Autodesk Fusion 360 part; units mm, degrees
(part 2 of 2)
sketch "Sketch2" plane through (0, 0, 4.8) normal (0, 0, 1) x (1, 0, 0)
  circle A0 centre (0, 0) radius 4.65
  line L0 (-0.4083, 0.4083) -> (-2.45, 0.4083)
  line L1 (-2.45, 0.4083) -> (-2.45, -0.4083)
  line L2 (-2.45, -0.4083) -> (-0.4083, -0.4083)
  line L3 (-0.4083, -0.4083) -> (-0.4083, -2.45)
  line L4 (-0.4083, -2.45) -> (0.4083, -2.45)
  line L5 (0.4083, -2.45) -> (0.4083, -0.4083)
  line L6 (0.4083, -0.4083) -> (2.45, -0.4083)
  line L7 (2.45, -0.4083) -> (2.45, 0.4083)
  line L8 (2.45, 0.4083) -> (0.4083, 0.4083)
  line L9 (0.4083, 0.4083) -> (0.4083, 2.45)
  line L10 (0.4083, 2.45) -> (-0.4083, 2.45)
  line L11 (-0.4083, 2.45) -> (-0.4083, 0.4083)
  dimension "d117" = 360
  dimension "d123" = 0.8167
  dimension "d124" = 4.9
  constraint perpendicular L0 L1
  constraint vertical L0.start L2.end
  constraint horizontal L2
  constraint coincident L0.start L11.end
  measures "d123" distance of L0 L2
  measures "d124" distance of L3.end L10
extrude "Extrude1" add sketch "Sketch2" against normal blind 3.05 draft -4 separate body contours L0 L1 L2 L3 L4 L5 L6 L7 L8 L9 L10 L11 makes body 3
draft "Draft1" angle -30 neutral plane through (0, 0, 4.8) pull (0, 0, 1) 4 faces at (2.3789, 0.065, 3.7833) (0.065, 2.3789, 3.7833) (-2.3789, 0.065, 3.7833) (0.065, -2.3789, 3.7833) on bodies 3
combine "Combine1" operation cut target body 1 tool bodies 2 3
sketch "Sketch6" plane through (0, 0, 4.8) normal (0, 0, 1) x (1, 0, 0)
  circle A0 centre (0, 0) radius 2.4838 construction
  line L0 (0, 0) -> (-1.7563, 1.7563) construction
  line L1 (-1.7563, 1.7563) -> (-0.4083, 0.49)
  line L2 (-0.4083, 0.49) -> (-0.49, 0.4083)
  line L3 (-0.49, 0.4083) -> (-1.7563, 1.7563)
  point P0 (-0.4083, 2.45)
  point P1 (-0.4083, 2.45)
  point P2 (-0.49, 0.49)
  point P3 (-0.4083, 0.49)
  point P4 (-0.49, 0.4083)
  constraint coincident A0.centre L0.start
  constraint coincident A0 P1
  constraint coincident A0 L0.end
  constraint coincident L0 P2
  constraint perpendicular L0 L2
  constraint coincident P1 P0
  constraint coincident P3 L1.end
  constraint coincident P4 L2.end
extrude "Extrude2" cut sketch "Sketch6" against normal blind 2.7 draft -30 bodies 1
pattern_circular "C-Pattern1" count 4 over 360 about axis through (0, 0, 1.75) along (0, 0, 1) of "Extrude2"
thread "Thread2" "ISO Metric profile 5.0 M5x0.8 M5x0.8 6g" major diameter 4.901 minor diameter 3.9895 pitch 0.8 angle 60 resizes the face on face at (-2.4969, 0.1246, -2.3333) on bodies 1
sketch "Sketch8" plane through (0, 0, 0) normal (0, 1, 0) x (1, 0, 0)
  line L0 (-1.7, 7.2) -> (-2.55, 7.2)
  line L1 (-2.55, 7.2) -> (-2.55, 6.35)
  line L2 (-2.55, 6.35) -> (-1.7, 7.2)
  point P0 (0, 7.2)
  dimension "d108" = 45
  dimension "d110" = 2.55
  dimension "d125" = 0.85
  constraint horizontal L0
  constraint perpendicular L0 L1
  constraint coincident L0 P0
  measures "d108" angle of L1 L2
  measures "d110" distance of L1 P0
  measures "d125" distance of L0 L1.end
revolve "Revolve3" cut sketch "Sketch8" angle 360 about axis through (0, 0, -7.2) along (0, 0, 1) bodies 1
equation "d9 = adsk_nomdia"
equation "d11 = adsk_headdia"
equation "adsk_nomlen = 12.00 mm"
equation "adsk_headh = 2.70 mm"
equation "adsk_headdia = 9.30 mm"
equation "adsk_nomdia = 5.00 mm"
equation "adsk_headang = 90.00 deg"
equation "adsk_phildia = 4.90 mm"
equation "d31 = -adsk_phildepth"
equation "adsk_philwidth = adsk_phildia / 6"
equation "adsk_phildepth = 3.05 mm"
equation "d61 = -adsk_headh"
equation "d68 = -adsk_phildepth * 0.8"
equation "adsk_startlen = adsk_pitch1"
equation "adsk_shnkdia = adsk_nomdia - 0.5 * adsk_pitch1"
equation "d89 = adsk_shnkdia"
equation "d90 = adsk_nomdia"
equation "d91 = adsk_pitch1"
equation "d93 = adsk_thrlen"
equation "adsk_thrlen = 7.30 mm"
equation "adsk_pitch1 = 0.80 mm"
equation "adsk_thrrun = 0.40 mm"
equation "d102 = ( adsk_nomdia / 2 ) * tan(90 deg - adsk_headang / 2) + adsk_headh"
equation "d110 = adsk_nomdia * 0.51"
equation "d120 = adsk_nomlen"
equation "d123 = adsk_philwidth"
equation "d124 = adsk_phildia"
equation "d125 = adsk_startlen + adsk_nomdia * 0.01"
equation "d126 = adsk_headang * 0.5"
equation "d127 = adsk_thrrun + adsk_thrlen"
equation "d130 = adsk_philwidth * 1.2"
equation "d131 = 0.03 * adsk_nomdia"

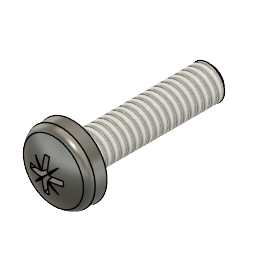
design "Pan Head Screw ISO 7045 - M2 x 8 - Z Steel 4.6 Plain"
description: Pan Head Screw ISO 7045 - M2 x 8 - Z
part number: ISO 7045 - M2 x 8 - Z Steel 4.6 Plain
Autodesk Fusion 360 part; units mm, degrees
sketch "Sketch1" plane through (0, 0, 0) normal (0, 1, 0) x (1, 0, 0)
  line L0 (-1, 0.8) -> (-1, 8)
  line L1 (-1, 8) -> (0, 8)
  line L2 (0, 8) -> (0, -1.6)
  line L3 (-0.8917, 0) -> (-2, 0)
  arc A0 (-1.9678, -0.9235) -> (0, -1.6) centre (0, 1.6) ccw
  line L4 (-1, 0.8) -> (-0.8917, 0.5678)
  line L5 (-0.8917, 0.5678) -> (-0.8917, 0)
  line L6 (-2, 0) -> (-1.9678, -0.9235)
  dimension "d9" = 2
  dimension "d75" = 4
  dimension "d98" = 1.7835
  dimension "d102" = 0.8
  dimension "d103" = 155
  dimension "d137" = 2
  dimension "d140" = 8
  dimension "d141" = 1.6
  constraint vertical L0
  constraint perpendicular L0 L1
  constraint coincident origin L3
  constraint coincident L2 A0.centre
  constraint vertical L2
  constraint vertical L5
  constraint coincident L3.start L5.end
  constraint coincident origin L2
  constraint perpendicular L3 L5
  constraint coincident A0.start L6.end
  measures "d102" distance of L3 L0.start
  measures "d103" angle of L4 L5
  measures "d137" angle of L2 L6
  measures "d140" distance of origin L1
  measures "d141" distance of L2.end L3
revolve "Revolve1" add sketch "Sketch1" angle 360 about axis through (0, 0, -8) along (0, 0, 1) makes body 1
ref_plane "WorkPlane1" through (0, 0, 1.6) normal (0, 0, 1) x (1, 0, 0)
sketch "Sketch7" plane through (0, 0, 1.6) normal (0, 0, 1) x (1, 0, 0)
  line L0 (0.18, -0.18) -> (0.18, 0.18)
  line L1 (0.18, 0.18) -> (-0.18, 0.18)
  line L2 (-0.18, 0.18) -> (-0.18, -0.18)
  line L3 (-0.18, -0.18) -> (0.18, -0.18)
  dimension "d150" = 0.36
  constraint vertical L0
  measures "d150" distance of L1 L3
extrude "Extrude4" add sketch "Sketch7" against normal blind 1.42 draft -10 separate body makes body 2
sketch "Sketch10" plane through (0, 0, 1.6) normal (0, 0, 1) x (1, 0, 0)
  line L0 (-0.15, 0.15) -> (-1.05, 0.15)
  line L1 (-1.05, 0.15) -> (-1.05, -0.15)
  line L2 (-1.05, -0.15) -> (-0.15, -0.15)
  line L3 (-0.15, -0.15) -> (-0.15, -1.05)
  line L4 (-0.15, -1.05) -> (0.15, -1.05)
  line L5 (0.15, -1.05) -> (0.15, -0.15)
  line L6 (0.15, -0.15) -> (1.05, -0.15)
  line L7 (1.05, -0.15) -> (1.05, 0.15)
  line L8 (1.05, 0.15) -> (0.15, 0.15)
  line L9 (0.15, 0.15) -> (0.15, 1.05)
  line L10 (0.15, 1.05) -> (-0.15, 1.05)
  line L11 (-0.15, 1.05) -> (-0.15, 0.15)
  dimension "d156" = 360
  dimension "d157" = 0.3
  dimension "d159" = 1.05
  constraint horizontal L0
  constraint perpendicular L0 L1
  constraint vertical L0.start L2.end
  constraint coincident L2.end L3.start
  measures "d157" distance of L0 L2
  measures "d159" distance of origin L1
extrude "Extrude1" add sketch "Sketch10" against normal blind 1.42 draft -6 separate body makes body 3
draft "Draft2" angle -30 neutral plane through (0, 0, 1.6) pull (0, 0, 1) 4 faces at (-0.0003, -1.0003, 1.1267) (-1.0003, 0.0003, 1.1267) (1.0003, 0.0003, 1.1267) (-0.0003, 1.0003, 1.1267) on bodies 3
combine "Combine1" operation cut target body 1 tool bodies 2 3
ref_plane "WorkPlane2" through (-0.9443, -0.1347, 1.4545) normal (0, 0, -1) x (-1, 0, 0)
sketch "Sketch8" plane through (-0.2873, 1.3933, 1.4545) normal (0, 0, -1) x (1, 0, 0)
  line L0 (0.2873, 1.3933) -> (1.104, 2.21)
  line L1 (2.0373, 1.3933) -> (22.7873, 1.3933)
  circle A0 centre (0.2873, 1.3933) radius 1
  line L2 (0.2873, 1.3933) -> (0.2873, 2.3933) construction
  line L3 (1.104, 2.21) -> (0.2873, 2.21) construction
  point P0 (0.2873, 1.3933)
  dimension "d117" = 45
  dimension "d148" = 0.8167
  constraint coincident P0 L0.start
  constraint coincident A0 L2.end
  constraint vertical L2
  constraint coincident L2 L3.end
  constraint perpendicular L2 L3
  measures "d117" angle of L0 L1
  measures "d148" distance of P0 L3
ref_plane "WorkPlane3" through (0.4084, -0.4084, 1.4545) normal (-0.664463, -0.664463, 0.34202) x (0.707107, -0.707107, 0)
sketch "Sketch9" plane through (0.7914, -0.4142, 2.1873) normal (-0.664463, -0.664463, 0.34202) x (0.707107, -0.707107, 0)
  line L0 (-0.8525, -0.7798) -> (0.3025, -0.7798)
  line L1 (0.3025, -0.7798) -> (0.3025, -0.1798)
  line L2 (0.3025, -0.1798) -> (-0.8525, -0.1798)
  line L3 (-0.8525, -0.1798) -> (-0.8525, -0.7798)
  point P0 (-0.8525, -0.7798)
  point P1 (0.3025, -0.7798)
  dimension "d149" = 0.6
  constraint coincident P0 L0.start
  constraint coincident P1 L1
  constraint coincident P1 L0.end
  constraint vertical L1
  constraint vertical L3
  measures "d149" distance of L0 L2
extrude "Extrude6" cut sketch "Sketch9" along normal blind 0.15 draft -50 bodies 1
pattern_circular "C-Pattern1" count 4 over 360 about axis through (0, 0, 1.75) along (0, 0, 1) of "Extrude6"
fillet "Fillet4" radius 0.5333 1 edges at (-1.8346, 0.7116, 0.9235) on bodies 1
thread "Thread1" "ISO Metric profile 2.0 M2x0.4 M2x0.4 6g" major diameter 1.9335 minor diameter 1.478 pitch 0.4 angle 60 resizes the face on face at (-0.995, 0.0996, -5.6) on bodies 1
fillet "Fillet5" radius 0.2 1 edges at (-0.8314, 0.3225, 0) on bodies 1
sketch "Sketch5" plane through (0, 0, 0) normal (0, 1, 0) x (1, 0, 0)
  line L0 (-1.02, 8) -> (-1.02, 7.7546)
  line L1 (-1.02, 7.7546) -> (-0.7546, 8)
  line L2 (0, 8) -> (0, -1.6)
  line L3 (-1.02, 8) -> (0, 8)
  dimension "d114" = 1.02
  dimension "d143" = 0.2454
  dimension "d144" = 0.2654
  constraint coincident L2.start L3.end
  constraint perpendicular L2 L3
  constraint coincident L1.end L3
  constraint perpendicular L0 L3
  measures "d114" distance of origin L0
  measures "d143" distance of L0.end L3
  measures "d144" distance of L0 L1.end
revolve "Revolve2" cut sketch "Sketch5" angle 360 about axis through (0, 0, -8) along (0, 0, 1) bodies 1
equation "d9 = adsk_nomdia"
equation "adsk_nomlen = 8.00 mm"
equation "adsk_headh = 1.60 mm"
equation "adsk_headdia = 4.00 mm"
equation "adsk_nomdia = 2.00 mm"
equation "adsk_phildia = 2.10 mm"
equation "d31 = -adsk_phildepth"
equation "adsk_philwidth = 0.30 mm"
equation "adsk_phildepth = 1.42 mm"
equation "d68 = -adsk_phildepth"
equation "d75 = adsk_headdia"
equation "d79 = adsk_headh"
equation "d86 = adsk_philwidth / 2"
equation "adsk_thrlen = 7.20 mm"
equation "d98 = adsk_shnkdia"
equation "adsk_shnkdia = 1.78349 mm"
equation "d102 = adsk_nomlen - adsk_thrlen"
equation "adsk_endpointdia = 1.50924 mm"
equation "adsk_startlen = 0.24538 mm"
equation "d114 = adsk_nomdia * 0.51"
equation "adsk_ovalrad = 3.20 mm"
equation "adsk_headang = 2.00 deg"
equation "adsk_headtoprad = adsk_headh / 3"
equation "d132 = adsk_midfillet"
equation "adsk_midfillet = adsk_nomdia * 0.1"
equation "d136 = adsk_headtoprad"
equation "d137 = adsk_headang"
equation "d140 = adsk_nomlen"
equation "d141 = adsk_headh"
equation "d142 = ( adsk_nomlen + adsk_headh ) - ( adsk_ovalrad )"
equation "d143 = adsk_startlen"
equation "d144 = ( adsk_nomdia * 0.51 ) - ( adsk_endpointdia / 2 )"
equation "d148 = ( adsk_phildia / 2 * 1.1 ) * cos(45 deg)"
equation "d149 = adsk_philwidth * 2"
equation "d150 = adsk_philwidth * 1.2"
equation "d157 = adsk_philwidth"
equation "d159 = adsk_phildia / 2"
